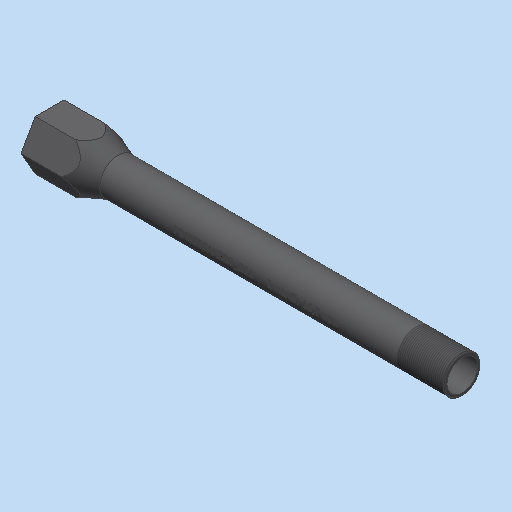
# Autodesk Inventor part: MN0555AN200_G11_100
Saved by Autodesk Inventor 2023.3 (Build 273359000, 359)
## iProperties
Created: 2012-10-29
Part Number: MN0555AN200_G11_100
Material: 1.2099 X5CrS12
Document SubType Name: Modeling
Designer: krt7an
Mass: 225.368 g
Surface Area: 273.759 cm^2
Volume: 28.7093 cm^3
Density: 7.85 g/cm^3
Description: =<RBPARTNOTITLE2>
Appearance: Stahl - rostfrei AnP
RBPARTNOTITLE1: manufactured part
RBPARTMADEOF: Ø31 x 220 (FM)
RBPARTNOTITLE2: Anfertigungsteil
RBPARTNO: SIEHE MNR
RBMATNO: =<Part Number>
RBMATERIAL: =<Material>
RBGBDIM_01: 0,000 mm
RBGBDIM_04: 0,000 mm
RBGBDIM_03: 0,000 mm
RBGBDIM_02: 0,000 mm
RBDRAWINGMISSINGSPEC: --
AnP_Kategorie: 1
RBGBREMARKSINDEX: E
RBSURFACE: --
AnP_Material: =<Material>
RBSURFACE2: --
MaxAbmaße: 26,847 x 31 x 220 (FM)
Author: krt7an
Keywords: =<RBPARTMADEOF>
Comments: =<RBSURFACE2>
Revision Number: 01
Autodesk Inventor part; units mm, degrees
ref_plane "YZ Plane" through (0, 0, 0) normal (1, 0, 0) x (0, 1, 0)
ref_plane "XY Plane" through (0, 0, 0) normal (0, 0, 1) x (1, 0, 0)
sketch "Skizze1" plane through (0, 0, 0) normal (0, 0, 1) x (1, 0, 0)
  line L0 (0, 0) -> (223, 0)
  line L1 (0, 0) -> (0, 10)
  line L2 (0, 10) -> (186, 10)
  line L3 (223, 0) -> (223, 15.5)
  line L4 (223, 15.5) -> (201.1111, 15.5)
  line L5 (201.1111, 15.5) -> (186, 10)
  dimension "d0" = 223
  dimension "d1" = 10
  dimension "d3" = 15.5
  dimension "d59" = 160
  dimension "d60" = 186
  constraints: 12 end point, 4 perpendicular, 1 horizontal
  measures "d0" distance of L0.start L0.end
  measures "d1" distance of L0.start L1.end
  measures "d3" distance of L0.end L3.end
  measures "d59" angle of L5 L2
  measures "d60" distance of L2.end L1.end
revolve "Umdrehung1" add sketch "Skizze1" angle 360 about axis through (0, 0, 0) along (1, 0, 0)
sketch "Skizze2" plane through (223, 0, 0) normal (1, 0, 0) x (0, 0, -1)
  circle A0 centre (0, 0) radius 15.5 projected
  line L0 (0, 15.5) -> (13.4234, 7.75)
  line L1 (13.4234, 7.75) -> (13.4234, -7.75)
  line L2 (13.4234, -7.75) -> (0, -15.5)
  line L3 (0, -15.5) -> (-13.4234, -7.75)
  line L4 (-13.4234, -7.75) -> (-13.4234, 7.75)
  line L5 (-13.4234, 7.75) -> (0, 15.5)
  line L6 (0, -21.7) -> (0, 21.7) projected
  constraints: 12 end point, 1 coincident, 1 point on line, 1 vertical alignment, 14 other
extrude "Extrusion1" cut sketch "Skizze2" against normal blind 30 contours A0 L1 | L0 A0 | A0 L2 | L5 A0 | A0 L3 | L4 A0
sketch "Skizze9" plane through (0, 0, 0) normal (-1, 0, 0) x (0, 0, 1)
  circle A0 centre (0, 0) radius 10 projected
  constraints: 1 coincident
hole "Bohrung1" at (0, 0, 0) direction (1, 0, 0) diameter 16.7 end through all
chamfer "Fase1" distance 0.5 angle 45 1 edges at (0, -10, 0)
sketch "Skizze11" plane through (223, -7.75, 13.4234) normal (1, 0, 0) x (0, 0, -1)
  circle A0 centre (13.4234, 7.75) radius 8.35 projected
  constraints: 1 coincident
hole "Bohrung2" at (223, 0, 0) direction (-1, 0, 0) diameter 19.177 depth 21 tip angle 118 thread size "7/8-9 UNC" class "2B" standard "ANSI Unified Screw Threads"
sketch "Skizze5" plane through (0, 0, 0) normal (0, 1, 0) x (-1, 0, 0)
  line L0 (40.4, 0) -> (-242.4, 0) projected
  line L1 (-202, 9.5885) -> (-202, -9.5885) projected
  line L2 (-201.2558, 8.35) -> (-201.2558, -8.35) projected
  line L3 (0, 8.35) -> (0, -8.35) projected
  line L4 (-202, 9.5885) -> (-188.4095, 1.4225)
  line L5 (-188.4095, 1.4225) -> (-188.4095, 0)
  line L6 (-202, 9.5885) -> (-202, 0)
  line L7 (-202, 0) -> (-188.4095, 0)
  point P0 (0, 0)
  dimension "d39" = 31
  dimension "d40" = 13.5905
  constraints: 8 end point, 1 collinear, 1 midpoint, 1 perpendicular, 1 point on line
  measures "d39" angle of L4 L0
  measures "d40" distance between parallel lines of L5 L1
revolve "Umdrehung2" cut sketch "Skizze5" angle 360 about axis through (-10, 0, 0) along (1, 0, 0)
thread "Gewinde4" size "M20x1" class "6g" standard "ISO Metric profile" length 25
sketch "Skizze7" plane through (223, -7.75, 13.4234) normal (1, 0, 0) x (0, 0, -1)
  circle A0 centre (13.4234, 7.75) radius 9.5885 projected
  circle A1 centre (13.4234, 7.75) radius 10
  dimension "d51" = 20
  constraints: 1 centre point, 1 coincident
  measures "d51" diameter of A1
extrude "Extrusion3" cut sketch "Skizze7" against normal blind 21
thread "Gewinde5" size "7/8-9 UNC" class "2B" standard "ANSI Unified Screw Threads" length 16
sketch "Skizze8" plane through (0, 0, 0) normal (-1, 0, 0) x (0, 0, 1)
  circle A0 centre (0, 0) radius 8.35 projected
  circle A1 centre (0, 0) radius 9.5 projected
  circle A2 centre (0, 0) radius 5.875
  dimension "d56" = 11.75
  constraints: 1 centre point, 1 coincident
  measures "d56" diameter of A2
extrude "Extrusion4" [suppressed]
ref_plane "Arbeitsebene3" through (93, 10, 0) normal (0, 1, 0) x (-1, 0, 0)
sketch "Skizze10" plane through (93, 10, 0) normal (0, 1, 0) x (-1, 0, 0)
  line L0 (-53, 2.25) -> (35.8221, 2.25) construction
  line L1 (35.8221, 2.25) -> (35.8221, -2.25) construction
  line L2 (35.8221, -2.25) -> (-53, -2.25) construction
  line L3 (-53, -2.25) -> (-53, 2.25) construction
  line L4 (-174.9, 0) -> (139.4, 0) projected
  line L5 (-93, 10) -> (-93, -10) projected
  line L6 (-49.6447, -1.4656) -> (-50.1098, -1.4656)
  line L7 (-50.1098, -1.4656) -> (-50.1098, 1.5494)
  line L8 (-50.1098, 1.5494) -> (-51.0231, -0.5012)
  line L9 (-51.0231, -0.5012) -> (-51.3067, -0.5012)
  line L10 (-51.3067, -0.5012) -> (-52.2115, 1.5494)
  line L11 (-52.2115, 1.5494) -> (-52.2115, -1.4656)
  line L12 (-52.2115, -1.4656) -> (-52.6455, -1.4656)
  line L13 (-52.6455, -1.4656) -> (-52.6455, 2.0344)
  line L14 (-52.6455, 2.0344) -> (-52.0101, 2.0344)
  line L15 (-52.0101, 2.0344) -> (-51.1365, 0.0859)
  line L16 (-51.1365, 0.0859) -> (-50.2913, 2.0344)
  line L17 (-50.2913, 2.0344) -> (-49.6447, 2.0344)
  line L18 (-49.6447, 2.0344) -> (-49.6447, -1.4656)
  line L19 (-45.9348, -1.4656) -> (-46.3999, -1.4656)
  line L20 (-46.3999, -1.4656) -> (-46.3999, 1.5494)
  line L21 (-46.3999, 1.5494) -> (-47.3132, -0.5012)
  line L22 (-47.3132, -0.5012) -> (-47.5968, -0.5012)
  line L23 (-47.5968, -0.5012) -> (-48.5016, 1.5494)
  line L24 (-48.5016, 1.5494) -> (-48.5016, -1.4656)
  line L25 (-48.5016, -1.4656) -> (-48.9356, -1.4656)
  line L26 (-48.9356, -1.4656) -> (-48.9356, 2.0344)
  line L27 (-48.9356, 2.0344) -> (-48.3002, 2.0344)
  line L28 (-48.3002, 2.0344) -> (-47.4267, 0.0859)
  line L29 (-47.4267, 0.0859) -> (-46.5814, 2.0344)
  line L30 (-46.5814, 2.0344) -> (-45.9348, 2.0344)
  line L31 (-45.9348, 2.0344) -> (-45.9348, -1.4656)
  spline S0 degree 2 poles (-43.1467, 0.2844) (-43.1467, -0.6572) (-43.6941, -1.5393) (-44.2642, -1.5393) knots 0 0 0 1 2 2 2
  spline S1 degree 2 poles (-44.2642, -1.5393) (-44.8428, -1.5393) (-45.3845, -0.6402) (-45.3845, 0.2816) knots 0 0 0 1 2 2 2
  spline S2 degree 2 poles (-45.3845, 0.2816) (-45.3845, 1.2289) (-44.8371, 2.1053) (-44.2642, 2.1053) knots 0 0 0 1 2 2 2
  spline S3 degree 2 poles (-44.2642, 2.1053) (-43.6884, 2.1053) (-43.1467, 1.1977) (-43.1467, 0.2844) knots 0 0 0 1 2 2 2
  spline S4 degree 2 poles (-43.748, -0.782) (-43.6799, -0.609) (-43.6232, -0.0758) (-43.6232, 0.2844) knots 0 0 0 1 2 2 2
  spline S5 degree 2 poles (-43.6232, 0.2844) (-43.6232, 0.6447) (-43.6799, 1.175) (-43.7508, 1.3537) knots 0 0 0 1 2 2 2
  spline S6 degree 2 poles (-43.7508, 1.3537) (-43.8217, 1.5324) (-44.0685, 1.7168) (-44.2642, 1.7168) knots 0 0 0 1 2 2 2
  spline S7 degree 2 poles (-44.2642, 1.7168) (-44.4599, 1.7168) (-44.7123, 1.5324) (-44.7861, 1.3481) knots 0 0 0 1 2 2 2
  spline S8 degree 2 poles (-44.7861, 1.3481) (-44.857, 1.1694) (-44.908, 0.6248) (-44.908, 0.2816) knots 0 0 0 1 2 2 2
  spline S9 degree 2 poles (-44.908, 0.2816) (-44.908, -0.0871) (-44.8626, -0.5806) (-44.7889, -0.7735) knots 0 0 0 1 2 2 2
  spline S10 degree 2 poles (-44.7889, -0.7735) (-44.7208, -0.955) (-44.4684, -1.1507) (-44.2642, -1.1507) knots 0 0 0 1 2 2 2
  spline S11 degree 2 poles (-44.2642, -1.1507) (-44.0713, -1.1507) (-43.8189, -0.9664) (-43.748, -0.782) knots 0 0 0 1 2 2 2
  spline S12 degree 2 poles (-40.577, -0.3537) (-40.577, -0.6062) (-40.7387, -1.0373) (-40.8861, -1.1961) knots 0 0 0 1 2 2 2
  spline S13 degree 2 poles (-40.8861, -1.1961) (-41.0336, -1.3549) (-41.4733, -1.5393) (-41.7455, -1.5393) knots 0 0 0 1 2 2 2
  spline S14 degree 2 poles (-41.7455, -1.5393) (-41.9951, -1.5393) (-42.483, -1.4287) (-42.6617, -1.3408) knots 0 0 0 1 2 2 2
  line L32 (-42.6617, -1.3408) -> (-42.6617, -0.8444)
  line L33 (-42.6617, -0.8444) -> (-42.6276, -0.8444)
  spline S15 degree 2 poles (-42.6276, -0.8444) (-42.5737, -0.8841) (-42.3724, -0.9862) (-42.2504, -1.0316) knots 0 0 0 1 2 2 2
  spline S16 degree 2 poles (-42.2504, -1.0316) (-42.1114, -1.0798) (-41.8817, -1.1337) (-41.737, -1.1337) knots 0 0 0 1 2 2 2
  spline S17 degree 2 poles (-41.737, -1.1337) (-41.5952, -1.1337) (-41.3286, -1.0316) (-41.2322, -0.921) knots 0 0 0 1 2 2 2
  spline S18 degree 2 poles (-41.2322, -0.921) (-41.1442, -0.816) (-41.0535, -0.5381) (-41.0535, -0.3509) knots 0 0 0 1 2 2 2
  spline S19 degree 2 poles (-41.0535, -0.3509) (-41.0535, -0.1637) (-41.1556, 0.0746) (-41.252, 0.154) knots 0 0 0 1 2 2 2
  spline S20 degree 2 poles (-41.252, 0.154) (-41.3513, 0.2419) (-41.6463, 0.3156) (-41.825, 0.3156) knots 0 0 0 1 2 2 2
  spline S21 degree 2 poles (-41.825, 0.3156) (-42.0178, 0.3156) (-42.4007, 0.2561) (-42.517, 0.2306) knots 0 0 0 1 2 2 2
  line L34 (-42.517, 0.2306) -> (-42.517, 2.0344)
  line L35 (-42.517, 2.0344) -> (-40.5968, 2.0344)
  line L36 (-40.5968, 2.0344) -> (-40.5968, 1.6232)
  line L37 (-40.5968, 1.6232) -> (-42.066, 1.6232)
  line L38 (-42.066, 1.6232) -> (-42.066, 0.69)
  spline S22 degree 2 poles (-42.066, 0.69) (-41.981, 0.7014) (-41.8165, 0.7099) (-41.7484, 0.7099) knots 0 0 0 1 2 2 2
  spline S23 degree 2 poles (-41.7484, 0.7099) (-41.4789, 0.7099) (-41.1074, 0.622) (-40.9372, 0.4915) knots 0 0 0 1 2 2 2
  spline S24 degree 2 poles (-40.9372, 0.4915) (-40.7642, 0.361) (-40.577, -0.0361) (-40.577, -0.3537) knots 0 0 0 1 2 2 2
  spline S25 degree 2 poles (-37.9506, -0.3537) (-37.9506, -0.6062) (-38.1122, -1.0373) (-38.2597, -1.1961) knots 0 0 0 1 2 2 2
  spline S26 degree 2 poles (-38.2597, -1.1961) (-38.4072, -1.3549) (-38.8468, -1.5393) (-39.1191, -1.5393) knots 0 0 0 1 2 2 2
  spline S27 degree 2 poles (-39.1191, -1.5393) (-39.3687, -1.5393) (-39.8566, -1.4287) (-40.0353, -1.3408) knots 0 0 0 1 2 2 2
  line L39 (-40.0353, -1.3408) -> (-40.0353, -0.8444)
  line L40 (-40.0353, -0.8444) -> (-40.0012, -0.8444)
  spline S28 degree 2 poles (-40.0012, -0.8444) (-39.9473, -0.8841) (-39.7459, -0.9862) (-39.624, -1.0316) knots 0 0 0 1 2 2 2
  spline S29 degree 2 poles (-39.624, -1.0316) (-39.485, -1.0798) (-39.2553, -1.1337) (-39.1106, -1.1337) knots 0 0 0 1 2 2 2
  spline S30 degree 2 poles (-39.1106, -1.1337) (-38.9688, -1.1337) (-38.7022, -1.0316) (-38.6058, -0.921) knots 0 0 0 1 2 2 2
  spline S31 degree 2 poles (-38.6058, -0.921) (-38.5178, -0.816) (-38.4271, -0.5381) (-38.4271, -0.3509) knots 0 0 0 1 2 2 2
  spline S32 degree 2 poles (-38.4271, -0.3509) (-38.4271, -0.1637) (-38.5292, 0.0746) (-38.6256, 0.154) knots 0 0 0 1 2 2 2
  spline S33 degree 2 poles (-38.6256, 0.154) (-38.7249, 0.2419) (-39.0199, 0.3156) (-39.1985, 0.3156) knots 0 0 0 1 2 2 2
  spline S34 degree 2 poles (-39.1985, 0.3156) (-39.3914, 0.3156) (-39.7743, 0.2561) (-39.8906, 0.2306) knots 0 0 0 1 2 2 2
  line L41 (-39.8906, 0.2306) -> (-39.8906, 2.0344)
  line L42 (-39.8906, 2.0344) -> (-37.9704, 2.0344)
  line L43 (-37.9704, 2.0344) -> (-37.9704, 1.6232)
  line L44 (-37.9704, 1.6232) -> (-39.4396, 1.6232)
  line L45 (-39.4396, 1.6232) -> (-39.4396, 0.69)
  spline S35 degree 2 poles (-39.4396, 0.69) (-39.3545, 0.7014) (-39.19, 0.7099) (-39.122, 0.7099) knots 0 0 0 1 2 2 2
  spline S36 degree 2 poles (-39.122, 0.7099) (-38.8525, 0.7099) (-38.481, 0.622) (-38.3108, 0.4915) knots 0 0 0 1 2 2 2
  spline S37 degree 2 poles (-38.3108, 0.4915) (-38.1378, 0.361) (-37.9506, -0.0361) (-37.9506, -0.3537) knots 0 0 0 1 2 2 2
  spline S38 degree 2 poles (-35.3241, -0.3537) (-35.3241, -0.6062) (-35.4858, -1.0373) (-35.6333, -1.1961) knots 0 0 0 1 2 2 2
  spline S39 degree 2 poles (-35.6333, -1.1961) (-35.7808, -1.3549) (-36.2204, -1.5393) (-36.4927, -1.5393) knots 0 0 0 1 2 2 2
  spline S40 degree 2 poles (-36.4927, -1.5393) (-36.7423, -1.5393) (-37.2301, -1.4287) (-37.4088, -1.3408) knots 0 0 0 1 2 2 2
  line L46 (-37.4088, -1.3408) -> (-37.4088, -0.8444)
  line L47 (-37.4088, -0.8444) -> (-37.3748, -0.8444)
  spline S41 degree 2 poles (-37.3748, -0.8444) (-37.3209, -0.8841) (-37.1195, -0.9862) (-36.9976, -1.0316) knots 0 0 0 1 2 2 2
  spline S42 degree 2 poles (-36.9976, -1.0316) (-36.8586, -1.0798) (-36.6288, -1.1337) (-36.4842, -1.1337) knots 0 0 0 1 2 2 2
  spline S43 degree 2 poles (-36.4842, -1.1337) (-36.3424, -1.1337) (-36.0758, -1.0316) (-35.9793, -0.921) knots 0 0 0 1 2 2 2
  spline S44 degree 2 poles (-35.9793, -0.921) (-35.8914, -0.816) (-35.8006, -0.5381) (-35.8006, -0.3509) knots 0 0 0 1 2 2 2
  spline S45 degree 2 poles (-35.8006, -0.3509) (-35.8006, -0.1637) (-35.9028, 0.0746) (-35.9992, 0.154) knots 0 0 0 1 2 2 2
  spline S46 degree 2 poles (-35.9992, 0.154) (-36.0985, 0.2419) (-36.3934, 0.3156) (-36.5721, 0.3156) knots 0 0 0 1 2 2 2
  spline S47 degree 2 poles (-36.5721, 0.3156) (-36.765, 0.3156) (-37.1479, 0.2561) (-37.2642, 0.2306) knots 0 0 0 1 2 2 2
  line L48 (-37.2642, 0.2306) -> (-37.2642, 2.0344)
  line L49 (-37.2642, 2.0344) -> (-35.344, 2.0344)
  line L50 (-35.344, 2.0344) -> (-35.344, 1.6232)
  line L51 (-35.344, 1.6232) -> (-36.8132, 1.6232)
  line L52 (-36.8132, 1.6232) -> (-36.8132, 0.69)
  spline S48 degree 2 poles (-36.8132, 0.69) (-36.7281, 0.7014) (-36.5636, 0.7099) (-36.4955, 0.7099) knots 0 0 0 1 2 2 2
  spline S49 degree 2 poles (-36.4955, 0.7099) (-36.2261, 0.7099) (-35.8545, 0.622) (-35.6844, 0.4915) knots 0 0 0 1 2 2 2
  spline S50 degree 2 poles (-35.6844, 0.4915) (-35.5113, 0.361) (-35.3241, -0.0361) (-35.3241, -0.3537) knots 0 0 0 1 2 2 2
  line L53 (-35.0972, -1.4656) -> (-33.9173, 2.0344)
  line L54 (-33.9173, 2.0344) -> (-33.3444, 2.0344)
  line L55 (-33.3444, 2.0344) -> (-32.1645, -1.4656)
  line L56 (-32.1645, -1.4656) -> (-32.6552, -1.4656)
  line L57 (-32.6552, -1.4656) -> (-32.9729, -0.487)
  line L58 (-32.9729, -0.487) -> (-34.3088, -0.487)
  line L59 (-34.3088, -0.487) -> (-34.6264, -1.4656)
  line L60 (-34.6264, -1.4656) -> (-35.0972, -1.4656)
  line L61 (-33.1005, -0.09) -> (-33.6422, 1.5579)
  line L62 (-33.6422, 1.5579) -> (-34.1811, -0.09)
  line L63 (-34.1811, -0.09) -> (-33.1005, -0.09)
  line L64 (-29.3282, -1.4656) -> (-29.8501, -1.4656)
  line L65 (-29.8501, -1.4656) -> (-31.3987, 1.5523)
  line L66 (-31.3987, 1.5523) -> (-31.3987, -1.4656)
  line L67 (-31.3987, -1.4656) -> (-31.8327, -1.4656)
  line L68 (-31.8327, -1.4656) -> (-31.8327, 2.0344)
  line L69 (-31.8327, 2.0344) -> (-31.1718, 2.0344)
  line L70 (-31.1718, 2.0344) -> (-29.7622, -0.7366)
  line L71 (-29.7622, -0.7366) -> (-29.7622, 2.0344)
  line L72 (-29.7622, 2.0344) -> (-29.3282, 2.0344)
  line L73 (-29.3282, 2.0344) -> (-29.3282, -1.4656)
  line L74 (-26.56, -1.4656) -> (-28.7184, -1.4656)
  line L75 (-28.7184, -1.4656) -> (-28.7184, -0.9692)
  spline S51 degree 2 poles (-28.7184, -0.9692) (-28.4858, -0.7508) (-28.0717, -0.3452) (-27.8732, -0.1268) knots 0 0 0 1 2 2 2
  spline S52 degree 2 poles (-27.8732, -0.1268) (-27.4733, 0.3128) (-27.1811, 0.8404) (-27.1811, 1.1212) knots 0 0 0 1 2 2 2
  spline S53 degree 2 poles (-27.1811, 1.1212) (-27.1811, 1.2686) (-27.2719, 1.4899) (-27.3541, 1.5608) knots 0 0 0 1 2 2 2
  spline S54 degree 2 poles (-27.3541, 1.5608) (-27.4364, 1.6317) (-27.6519, 1.7026) (-27.7824, 1.7026) knots 0 0 0 1 2 2 2
  spline S55 degree 2 poles (-27.7824, 1.7026) (-27.9072, 1.7026) (-28.1625, 1.6402) (-28.2788, 1.592) knots 0 0 0 1 2 2 2
  spline S56 degree 2 poles (-28.2788, 1.592) (-28.378, 1.5523) (-28.5624, 1.4388) (-28.6191, 1.3991) knots 0 0 0 1 2 2 2
  line L76 (-28.6191, 1.3991) -> (-28.6447, 1.3991)
  line L77 (-28.6447, 1.3991) -> (-28.6447, 1.8983)
  spline S57 degree 2 poles (-28.6447, 1.8983) (-28.5, 1.9692) (-27.981, 2.1082) (-27.7484, 2.1082) knots 0 0 0 1 2 2 2
  spline S58 degree 2 poles (-27.7484, 2.1082) (-27.2577, 2.1082) (-26.7046, 1.5891) (-26.7046, 1.1467) knots 0 0 0 1 2 2 2
  spline S59 degree 2 poles (-26.7046, 1.1467) (-26.7046, 0.9396) (-26.8011, 0.5936) (-26.8861, 0.4461) knots 0 0 0 1 2 2 2
  spline S60 degree 2 poles (-26.8861, 0.4461) (-26.9712, 0.2929) (-27.218, -0.0077) (-27.3541, -0.1524) knots 0 0 0 1 2 2 2
  spline S61 degree 2 poles (-27.3541, -0.1524) (-27.5754, -0.3934) (-28.1171, -0.9096) (-28.2788, -1.06) knots 0 0 0 1 2 2 2
  line L78 (-28.2788, -1.06) -> (-26.56, -1.06)
  line L79 (-26.56, -1.06) -> (-26.56, -1.4656)
  spline S62 degree 2 poles (-23.9137, 0.2844) (-23.9137, -0.6572) (-24.4611, -1.5393) (-25.0312, -1.5393) knots 0 0 0 1 2 2 2
  spline S63 degree 2 poles (-25.0312, -1.5393) (-25.6098, -1.5393) (-26.1515, -0.6402) (-26.1515, 0.2816) knots 0 0 0 1 2 2 2
  spline S64 degree 2 poles (-26.1515, 0.2816) (-26.1515, 1.2289) (-25.6041, 2.1053) (-25.0312, 2.1053) knots 0 0 0 1 2 2 2
  spline S65 degree 2 poles (-25.0312, 2.1053) (-24.4554, 2.1053) (-23.9137, 1.1977) (-23.9137, 0.2844) knots 0 0 0 1 2 2 2
  spline S66 degree 2 poles (-24.515, -0.782) (-24.4469, -0.609) (-24.3902, -0.0758) (-24.3902, 0.2844) knots 0 0 0 1 2 2 2
  spline S67 degree 2 poles (-24.3902, 0.2844) (-24.3902, 0.6447) (-24.4469, 1.175) (-24.5178, 1.3537) knots 0 0 0 1 2 2 2
  spline S68 degree 2 poles (-24.5178, 1.3537) (-24.5887, 1.5324) (-24.8355, 1.7168) (-25.0312, 1.7168) knots 0 0 0 1 2 2 2
  spline S69 degree 2 poles (-25.0312, 1.7168) (-25.2269, 1.7168) (-25.4793, 1.5324) (-25.5531, 1.3481) knots 0 0 0 1 2 2 2
  spline S70 degree 2 poles (-25.5531, 1.3481) (-25.624, 1.1694) (-25.675, 0.6248) (-25.675, 0.2816) knots 0 0 0 1 2 2 2
  spline S71 degree 2 poles (-25.675, 0.2816) (-25.675, -0.0871) (-25.6297, -0.5806) (-25.5559, -0.7735) knots 0 0 0 1 2 2 2
  spline S72 degree 2 poles (-25.5559, -0.7735) (-25.4878, -0.955) (-25.2354, -1.1507) (-25.0312, -1.1507) knots 0 0 0 1 2 2 2
  spline S73 degree 2 poles (-25.0312, -1.1507) (-24.8383, -1.1507) (-24.5859, -0.9664) (-24.515, -0.782) knots 0 0 0 1 2 2 2
  spline S74 degree 2 poles (-21.2873, 0.2844) (-21.2873, -0.6572) (-21.8347, -1.5393) (-22.4048, -1.5393) knots 0 0 0 1 2 2 2
  spline S75 degree 2 poles (-22.4048, -1.5393) (-22.9834, -1.5393) (-23.5251, -0.6402) (-23.5251, 0.2816) knots 0 0 0 1 2 2 2
  spline S76 degree 2 poles (-23.5251, 0.2816) (-23.5251, 1.2289) (-22.9777, 2.1053) (-22.4048, 2.1053) knots 0 0 0 1 2 2 2
  spline S77 degree 2 poles (-22.4048, 2.1053) (-21.829, 2.1053) (-21.2873, 1.1977) (-21.2873, 0.2844) knots 0 0 0 1 2 2 2
  spline S78 degree 2 poles (-21.8886, -0.782) (-21.8205, -0.609) (-21.7638, -0.0758) (-21.7638, 0.2844) knots 0 0 0 1 2 2 2
  spline S79 degree 2 poles (-21.7638, 0.2844) (-21.7638, 0.6447) (-21.8205, 1.175) (-21.8914, 1.3537) knots 0 0 0 1 2 2 2
  spline S80 degree 2 poles (-21.8914, 1.3537) (-21.9623, 1.5324) (-22.2091, 1.7168) (-22.4048, 1.7168) knots 0 0 0 1 2 2 2
  spline S81 degree 2 poles (-22.4048, 1.7168) (-22.6005, 1.7168) (-22.8529, 1.5324) (-22.9267, 1.3481) knots 0 0 0 1 2 2 2
  spline S82 degree 2 poles (-22.9267, 1.3481) (-22.9976, 1.1694) (-23.0486, 0.6248) (-23.0486, 0.2816) knots 0 0 0 1 2 2 2
  spline S83 degree 2 poles (-23.0486, 0.2816) (-23.0486, -0.0871) (-23.0032, -0.5806) (-22.9295, -0.7735) knots 0 0 0 1 2 2 2
  spline S84 degree 2 poles (-22.9295, -0.7735) (-22.8614, -0.955) (-22.609, -1.1507) (-22.4048, -1.1507) knots 0 0 0 1 2 2 2
  spline S85 degree 2 poles (-22.4048, -1.1507) (-22.2119, -1.1507) (-21.9595, -0.9664) (-21.8886, -0.782) knots 0 0 0 1 2 2 2
  line L80 (-18.4311, -2.169) -> (-21.1313, -2.169)
  line L81 (-21.1313, -2.169) -> (-21.1313, -1.8655)
  line L82 (-21.1313, -1.8655) -> (-18.4311, -1.8655)
  line L83 (-18.4311, -1.8655) -> (-18.4311, -2.169)
  spline S86 degree 2 poles (-16.6471, -1.5336) (-17.0186, -1.5336) (-17.6341, -1.3067) (-17.8553, -1.077) knots 0 0 0 1 2 2 2
  spline S87 degree 2 poles (-17.8553, -1.077) (-18.0766, -0.8444) (-18.312, -0.158) (-18.312, 0.2873) knots 0 0 0 1 2 2 2
  spline S88 degree 2 poles (-18.312, 0.2873) (-18.312, 0.7099) (-18.0737, 1.3793) (-17.8525, 1.6175) knots 0 0 0 1 2 2 2
  spline S89 degree 2 poles (-17.8525, 1.6175) (-17.6398, 1.8472) (-17.0158, 2.0968) (-16.6442, 2.0968) knots 0 0 0 1 2 2 2
  spline S90 degree 2 poles (-16.6442, 2.0968) (-16.4656, 2.0968) (-16.1422, 2.0458) (-15.9947, 2.0004) knots 0 0 0 1 2 2 2
  spline S91 degree 2 poles (-15.9947, 2.0004) (-15.8756, 1.9664) (-15.5863, 1.8416) (-15.4984, 1.7962) knots 0 0 0 1 2 2 2
  line L84 (-15.4984, 1.7962) -> (-15.4984, 1.2346)
  line L85 (-15.4984, 1.2346) -> (-15.5381, 1.2346)
  spline S92 degree 2 poles (-15.5381, 1.2346) (-15.626, 1.3112) (-15.8104, 1.4502) (-15.9806, 1.5296) knots 0 0 0 1 2 2 2
  spline S93 degree 2 poles (-15.9806, 1.5296) (-16.1224, 1.6005) (-16.4883, 1.6941) (-16.6981, 1.6941) knots 0 0 0 1 2 2 2
  spline S94 degree 2 poles (-16.6981, 1.6941) (-17.203, 1.6941) (-17.827, 0.934) (-17.827, 0.3015) knots 0 0 0 1 2 2 2
  spline S95 degree 2 poles (-17.827, 0.3015) (-17.827, -0.0502) (-17.6625, -0.5778) (-17.5065, -0.7593) knots 0 0 0 1 2 2 2
  spline S96 degree 2 poles (-17.5065, -0.7593) (-17.3562, -0.9408) (-16.9307, -1.1309) (-16.6641, -1.1309) knots 0 0 0 1 2 2 2
  spline S97 degree 2 poles (-16.6641, -1.1309) (-16.4684, -1.1309) (-16.077, -1.0741) (-15.9437, -1.0174) knots 0 0 0 1 2 2 2
  line L86 (-15.9437, -1.0174) -> (-15.9437, -0.1126)
  line L87 (-15.9437, -0.1126) -> (-16.7549, -0.1126)
  line L88 (-16.7549, -0.1126) -> (-16.7549, 0.2958)
  line L89 (-16.7549, 0.2958) -> (-15.4842, 0.2958)
  line L90 (-15.4842, 0.2958) -> (-15.4842, -1.233)
  spline S98 degree 2 poles (-15.4842, -1.233) (-15.5721, -1.2727) (-15.8728, -1.3947) (-16.0004, -1.4315) knots 0 0 0 1 2 2 2
  spline S99 degree 2 poles (-16.0004, -1.4315) (-16.1734, -1.4826) (-16.4514, -1.5336) (-16.6471, -1.5336) knots 0 0 0 1 2 2 2
  line L91 (-13.0166, -1.4656) -> (-14.7241, -1.4656)
  line L92 (-14.7241, -1.4656) -> (-14.7241, -1.1082)
  line L93 (-14.7241, -1.1082) -> (-14.0887, -1.1082)
  line L94 (-14.0887, -1.1082) -> (-14.0887, 1.2374)
  line L95 (-14.0887, 1.2374) -> (-14.7241, 1.2374)
  line L96 (-14.7241, 1.2374) -> (-14.7241, 1.5579)
  spline S100 degree 2 poles (-14.7241, 1.5579) (-14.3639, 1.5579) (-14.0235, 1.7622) (-14.0008, 2.0458) knots 0 0 0 1 2 2 2
  line L97 (-14.0008, 2.0458) -> (-13.6378, 2.0458)
  line L98 (-13.6378, 2.0458) -> (-13.6378, -1.1082)
  line L99 (-13.6378, -1.1082) -> (-13.0166, -1.1082)
  line L100 (-13.0166, -1.1082) -> (-13.0166, -1.4656)
  line L101 (-10.3902, -1.4656) -> (-12.0977, -1.4656)
  line L102 (-12.0977, -1.4656) -> (-12.0977, -1.1082)
  line L103 (-12.0977, -1.1082) -> (-11.4623, -1.1082)
  line L104 (-11.4623, -1.1082) -> (-11.4623, 1.2374)
  line L105 (-11.4623, 1.2374) -> (-12.0977, 1.2374)
  line L106 (-12.0977, 1.2374) -> (-12.0977, 1.5579)
  spline S101 degree 2 poles (-12.0977, 1.5579) (-11.7374, 1.5579) (-11.3971, 1.7622) (-11.3744, 2.0458) knots 0 0 0 1 2 2 2
  line L107 (-11.3744, 2.0458) -> (-11.0113, 2.0458)
  line L108 (-11.0113, 2.0458) -> (-11.0113, -1.1082)
  line L109 (-11.0113, -1.1082) -> (-10.3902, -1.1082)
  line L110 (-10.3902, -1.1082) -> (-10.3902, -1.4656)
  line L111 (-0.9113, -1.4656) -> (-2.267, -1.4656)
  line L112 (-2.267, -1.4656) -> (-2.267, -1.1082)
  line L113 (-2.267, -1.1082) -> (-1.8217, -1.1082)
  line L114 (-1.8217, -1.1082) -> (-1.8217, 1.6771)
  line L115 (-1.8217, 1.6771) -> (-2.267, 1.6771)
  line L116 (-2.267, 1.6771) -> (-2.267, 2.0344)
  line L117 (-2.267, 2.0344) -> (-0.9113, 2.0344)
  line L118 (-0.9113, 2.0344) -> (-0.9113, 1.6771)
  line L119 (-0.9113, 1.6771) -> (-1.3566, 1.6771)
  line L120 (-1.3566, 1.6771) -> (-1.3566, -1.1082)
  line L121 (-1.3566, -1.1082) -> (-0.9113, -1.1082)
  line L122 (-0.9113, -1.1082) -> (-0.9113, -1.4656)
  line L123 (1.6925, -1.4656) -> (1.25, -1.4656)
  line L124 (1.25, -1.4656) -> (1.25, 0.032)
  spline S102 degree 2 poles (1.25, 0.032) (1.25, 0.2135) (1.216, 0.5255) (1.1649, 0.6191) knots 0 0 0 1 2 2 2
  spline S103 degree 2 poles (1.1649, 0.6191) (1.111, 0.7184) (0.9182, 0.8148) (0.7536, 0.8148) knots 0 0 0 1 2 2 2
  spline S104 degree 2 poles (0.7536, 0.8148) (0.5891, 0.8148) (0.2403, 0.639) (0.0729, 0.4972) knots 0 0 0 1 2 2 2
  line L125 (0.0729, 0.4972) -> (0.0729, -1.4656)
  line L126 (0.0729, -1.4656) -> (-0.3695, -1.4656)
  line L127 (-0.3695, -1.4656) -> (-0.3695, 1.1609)
  line L128 (-0.3695, 1.1609) -> (0.0729, 1.1609)
  line L129 (0.0729, 1.1609) -> (0.0729, 0.8687)
  spline S105 degree 2 poles (0.0729, 0.8687) (0.2715, 1.0474) (0.6544, 1.2346) (0.8699, 1.2346) knots 0 0 0 1 2 2 2
  spline S106 degree 2 poles (0.8699, 1.2346) (1.2557, 1.2346) (1.6925, 0.7241) (1.6925, 0.2391) knots 0 0 0 1 2 2 2
  line L130 (1.6925, 0.2391) -> (1.6925, -1.4656)
  line L131 (4.3756, -1.4656) -> (3.9331, -1.4656)
  line L132 (3.9331, -1.4656) -> (3.9331, 0.032)
  spline S107 degree 2 poles (3.9331, 0.032) (3.9331, 0.2135) (3.8991, 0.5255) (3.8481, 0.6191) knots 0 0 0 1 2 2 2
  spline S108 degree 2 poles (3.8481, 0.6191) (3.7942, 0.7184) (3.6013, 0.8148) (3.4368, 0.8148) knots 0 0 0 1 2 2 2
  spline S109 degree 2 poles (3.4368, 0.8148) (3.2723, 0.8148) (2.9234, 0.639) (2.7561, 0.4972) knots 0 0 0 1 2 2 2
  line L133 (2.7561, 0.4972) -> (2.7561, -1.4656)
  line L134 (2.7561, -1.4656) -> (2.3136, -1.4656)
  line L135 (2.3136, -1.4656) -> (2.3136, 1.1609)
  line L136 (2.3136, 1.1609) -> (2.7561, 1.1609)
  line L137 (2.7561, 1.1609) -> (2.7561, 0.8687)
  spline S110 degree 2 poles (2.7561, 0.8687) (2.9546, 1.0474) (3.3375, 1.2346) (3.5531, 1.2346) knots 0 0 0 1 2 2 2
  spline S111 degree 2 poles (3.5531, 1.2346) (3.9388, 1.2346) (4.3756, 0.7241) (4.3756, 0.2391) knots 0 0 0 1 2 2 2
  line L138 (4.3756, 0.2391) -> (4.3756, -1.4656)
  spline S112 degree 2 poles (6.137, -1.5251) (5.5073, -1.5251) (4.8152, -0.8189) (4.8152, -0.1665) knots 0 0 0 1 2 2 2
  spline S113 degree 2 poles (4.8152, -0.1665) (4.8152, 0.4745) (5.4874, 1.2346) (6.0292, 1.2346) knots 0 0 0 1 2 2 2
  spline S114 degree 2 poles (6.0292, 1.2346) (6.2731, 1.2346) (6.6503, 1.0928) (6.7893, 0.9425) knots 0 0 0 1 2 2 2
  spline S115 degree 2 poles (6.7893, 0.9425) (6.9311, 0.7921) (7.0814, 0.3582) (7.0814, 0.0434) knots 0 0 0 1 2 2 2
  line L139 (7.0814, 0.0434) -> (7.0814, -0.1977)
  line L140 (7.0814, -0.1977) -> (5.2634, -0.1977)
  spline S116 degree 2 poles (5.2634, -0.1977) (5.2634, -0.6544) (5.7229, -1.1394) (6.1313, -1.1394) knots 0 0 0 1 2 2 2
  spline S117 degree 2 poles (6.1313, -1.1394) (6.2759, -1.1394) (6.5567, -1.0741) (6.6702, -1.0231) knots 0 0 0 1 2 2 2
  spline S118 degree 2 poles (6.6702, -1.0231) (6.7893, -0.9664) (6.9538, -0.8671) (7.0077, -0.8217) knots 0 0 0 1 2 2 2
  line L141 (7.0077, -0.8217) -> (7.0332, -0.8217)
  line L142 (7.0332, -0.8217) -> (7.0332, -1.3039)
  spline S119 degree 2 poles (7.0332, -1.3039) (6.9566, -1.3351) (6.7241, -1.4259) (6.6333, -1.4514) knots 0 0 0 1 2 2 2
  spline S120 degree 2 poles (6.6333, -1.4514) (6.5057, -1.4882) (6.2958, -1.5251) (6.137, -1.5251) knots 0 0 0 1 2 2 2
  spline S121 degree 2 poles (6.6503, 0.1398) (6.6447, 0.3185) (6.5709, 0.5794) (6.5, 0.6673) knots 0 0 0 1 2 2 2
  spline S122 degree 2 poles (6.5, 0.6673) (6.4234, 0.7666) (6.1823, 0.8716) (6.0036, 0.8716) knots 0 0 0 1 2 2 2
  spline S123 degree 2 poles (6.0036, 0.8716) (5.8278, 0.8716) (5.581, 0.7666) (5.4789, 0.6645) knots 0 0 0 1 2 2 2
  spline S124 degree 2 poles (5.4789, 0.6645) (5.3797, 0.5596) (5.2776, 0.3071) (5.2634, 0.1398) knots 0 0 0 1 2 2 2
  line L143 (5.2634, 0.1398) -> (6.6503, 0.1398)
  line L144 (9.5916, -1.4656) -> (9.1491, -1.4656)
  line L145 (9.1491, -1.4656) -> (9.1491, 0.032)
  spline S125 degree 2 poles (9.1491, 0.032) (9.1491, 0.2135) (9.1151, 0.5255) (9.064, 0.6191) knots 0 0 0 1 2 2 2
  spline S126 degree 2 poles (9.064, 0.6191) (9.0101, 0.7184) (8.8173, 0.8148) (8.6528, 0.8148) knots 0 0 0 1 2 2 2
  spline S127 degree 2 poles (8.6528, 0.8148) (8.4882, 0.8148) (8.1394, 0.639) (7.972, 0.4972) knots 0 0 0 1 2 2 2
  line L146 (7.972, 0.4972) -> (7.972, -1.4656)
  line L147 (7.972, -1.4656) -> (7.5296, -1.4656)
  line L148 (7.5296, -1.4656) -> (7.5296, 1.1609)
  line L149 (7.5296, 1.1609) -> (7.972, 1.1609)
  line L150 (7.972, 1.1609) -> (7.972, 0.8687)
  spline S128 degree 2 poles (7.972, 0.8687) (8.1706, 1.0474) (8.5535, 1.2346) (8.769, 1.2346) knots 0 0 0 1 2 2 2
  spline S129 degree 2 poles (8.769, 1.2346) (9.1548, 1.2346) (9.5916, 0.7241) (9.5916, 0.2391) knots 0 0 0 1 2 2 2
  line L151 (9.5916, 0.2391) -> (9.5916, -1.4656)
  spline S130 degree 2 poles (13.1426, 0.2844) (13.1426, -0.5835) (12.2974, -1.5393) (11.594, -1.5393) knots 0 0 0 1 2 2 2
  spline S131 degree 2 poles (11.594, -1.5393) (11.3359, -1.5393) (10.8906, -1.4032) (10.7119, -1.2784) knots 0 0 0 1 2 2 2
  line L152 (10.7119, -1.2784) -> (10.3999, -1.7378)
  line L153 (10.3999, -1.7378) -> (10.0539, -1.7378)
  line L154 (10.0539, -1.7378) -> (10.4964, -1.0855)
  spline S132 degree 2 poles (10.4964, -1.0855) (10.2865, -0.8529) (10.0482, -0.1665) (10.0482, 0.2844) knots 0 0 0 1 2 2 2
  spline S133 degree 2 poles (10.0482, 0.2844) (10.0482, 1.1495) (10.8963, 2.1082) (11.594, 2.1082) knots 0 0 0 1 2 2 2
  spline S134 degree 2 poles (11.594, 2.1082) (11.8635, 2.1082) (12.2832, 1.9777) (12.4704, 1.8501) knots 0 0 0 1 2 2 2
  line L155 (12.4704, 1.8501) -> (12.7399, 2.25)
  line L156 (12.7399, 2.25) -> (13.0887, 2.25)
  line L157 (13.0887, 2.25) -> (12.686, 1.66)
  spline S135 degree 2 poles (12.686, 1.66) (12.9015, 1.4275) (13.1426, 0.7524) (13.1426, 0.2844) knots 0 0 0 1 2 2 2
  spline S136 degree 2 poles (12.6633, 0.2844) (12.6633, 0.6078) (12.5328, 1.1155) (12.425, 1.2828) knots 0 0 0 1 2 2 2
  line L158 (12.425, 1.2828) -> (10.9502, -0.921)
  spline S137 degree 2 poles (10.9502, -0.921) (11.0835, -1.0288) (11.3841, -1.1365) (11.5968, -1.1365) knots 0 0 0 1 2 2 2
  spline S138 degree 2 poles (11.5968, -1.1365) (12.0818, -1.1365) (12.6633, -0.4048) (12.6633, 0.2844) knots 0 0 0 1 2 2 2
  spline S139 degree 2 poles (12.2322, 1.4955) (12.1102, 1.6005) (11.7897, 1.7054) (11.5968, 1.7054) knots 0 0 0 1 2 2 2
  spline S140 degree 2 poles (11.5968, 1.7054) (11.109, 1.7054) (10.5276, 0.9822) (10.5276, 0.2844) knots 0 0 0 1 2 2 2
  spline S141 degree 2 poles (10.5276, 0.2844) (10.5276, -0.0332) (10.6495, -0.5267) (10.7601, -0.7026) knots 0 0 0 1 2 2 2
  line L159 (10.7601, -0.7026) -> (12.2322, 1.4955)
  line L160 (14.4303, -1.4656) -> (13.8687, -1.4656)
  line L161 (13.8687, -1.4656) -> (13.8687, -0.7962)
  line L162 (13.8687, -0.7962) -> (14.4303, -0.7962)
  line L163 (14.4303, -0.7962) -> (14.4303, -1.4656)
  line L164 (14.4303, 0.4915) -> (13.8687, 0.4915)
  line L165 (13.8687, 0.4915) -> (13.8687, 1.1609)
  line L166 (13.8687, 1.1609) -> (14.4303, 1.1609)
  line L167 (14.4303, 1.1609) -> (14.4303, 0.4915)
  line L168 (18.7415, -1.4656) -> (17.034, -1.4656)
  line L169 (17.034, -1.4656) -> (17.034, -1.1082)
  line L170 (17.034, -1.1082) -> (17.6694, -1.1082)
  line L171 (17.6694, -1.1082) -> (17.6694, 1.2374)
  line L172 (17.6694, 1.2374) -> (17.034, 1.2374)
  line L173 (17.034, 1.2374) -> (17.034, 1.5579)
  spline S142 degree 2 poles (17.034, 1.5579) (17.3942, 1.5579) (17.7346, 1.7622) (17.7573, 2.0458) knots 0 0 0 1 2 2 2
  line L174 (17.7573, 2.0458) -> (18.1203, 2.0458)
  line L175 (18.1203, 2.0458) -> (18.1203, -1.1082)
  line L176 (18.1203, -1.1082) -> (18.7415, -1.1082)
  line L177 (18.7415, -1.1082) -> (18.7415, -1.4656)
  spline S143 degree 2 poles (21.5976, -0.331) (21.5976, -0.6005) (21.419, -1.0571) (21.2686, -1.2103) knots 0 0 0 1 2 2 2
  spline S144 degree 2 poles (21.2686, -1.2103) (21.1126, -1.372) (20.7212, -1.5393) (20.4858, -1.5393) knots 0 0 0 1 2 2 2
  spline S145 degree 2 poles (20.4858, -1.5393) (20.2504, -1.5393) (19.8618, -1.3805) (19.7143, -1.2216) knots 0 0 0 1 2 2 2
  spline S146 degree 2 poles (19.7143, -1.2216) (19.5328, -1.0316) (19.3286, -0.3934) (19.3286, 0.0717) knots 0 0 0 1 2 2 2
  spline S147 degree 2 poles (19.3286, 0.0717) (19.3286, 0.5284) (19.5158, 1.263) (19.7115, 1.5353) knots 0 0 0 1 2 2 2
  spline S148 degree 2 poles (19.7115, 1.5353) (19.9015, 1.8019) (20.5028, 2.0997) (20.8971, 2.0997) knots 0 0 0 1 2 2 2
  spline S149 degree 2 poles (20.8971, 2.0997) (21.0134, 2.0997) (21.2176, 2.077) (21.2942, 2.0515) knots 0 0 0 1 2 2 2
  line L178 (21.2942, 2.0515) -> (21.2942, 1.6005)
  line L179 (21.2942, 1.6005) -> (21.2743, 1.6005)
  spline S150 degree 2 poles (21.2743, 1.6005) (21.2091, 1.6345) (20.9708, 1.6941) (20.8347, 1.6941) knots 0 0 0 1 2 2 2
  spline S151 degree 2 poles (20.8347, 1.6941) (20.3979, 1.6941) (19.8618, 1.1041) (19.8108, 0.5255) knots 0 0 0 1 2 2 2
  spline S152 degree 2 poles (19.8108, 0.5255) (19.9781, 0.6418) (20.3298, 0.7694) (20.5397, 0.7694) knots 0 0 0 1 2 2 2
  spline S153 degree 2 poles (20.5397, 0.7694) (20.7439, 0.7694) (21.0502, 0.6872) (21.2176, 0.5624) knots 0 0 0 1 2 2 2
  spline S154 degree 2 poles (21.2176, 0.5624) (21.4105, 0.4177) (21.5976, -0.0304) (21.5976, -0.331) knots 0 0 0 1 2 2 2
  spline S155 degree 2 poles (21.1211, -0.3509) (21.1211, -0.1353) (21.0077, 0.1568) (20.8829, 0.2589) knots 0 0 0 1 2 2 2
  spline S156 degree 2 poles (20.8829, 0.2589) (20.7893, 0.3327) (20.5567, 0.3809) (20.4348, 0.3809) knots 0 0 0 1 2 2 2
  spline S157 degree 2 poles (20.4348, 0.3809) (20.2703, 0.3809) (19.9611, 0.2816) (19.8108, 0.188) knots 0 0 0 1 2 2 2
  spline S158 degree 2 poles (19.8108, 0.188) (19.8079, 0.137) (19.8023, 0.0405) (19.8023, -0.0332) knots 0 0 0 1 2 2 2
  spline S159 degree 2 poles (19.8023, -0.0332) (19.8023, -0.3963) (19.9441, -0.8416) (20.0519, -0.9579) knots 0 0 0 1 2 2 2
  spline S160 degree 2 poles (20.0519, -0.9579) (20.1511, -1.0685) (20.3667, -1.1564) (20.4887, -1.1564) knots 0 0 0 1 2 2 2
  spline S161 degree 2 poles (20.4887, -1.1564) (20.7723, -1.1564) (21.1211, -0.7536) (21.1211, -0.3509) knots 0 0 0 1 2 2 2
  line L180 (22.9307, -0.7962) -> (22.2727, -2.3363)
  line L181 (22.2727, -2.3363) -> (21.9295, -2.3363)
  line L182 (21.9295, -2.3363) -> (22.3436, -0.7962)
  line L183 (22.3436, -0.7962) -> (22.9307, -0.7962)
  line L184 (25.6677, 1.5097) -> (24.1532, -1.4656)
  line L185 (24.1532, -1.4656) -> (23.654, -1.4656)
  line L186 (23.654, -1.4656) -> (25.2536, 1.6232)
  line L187 (25.2536, 1.6232) -> (23.4469, 1.6232)
  line L188 (23.4469, 1.6232) -> (23.4469, 2.0344)
  line L189 (23.4469, 2.0344) -> (25.6677, 2.0344)
  line L190 (25.6677, 2.0344) -> (25.6677, 1.5097)
  line L191 (30.6426, -1.4656) -> (30.6426, 0.0547)
  spline S162 degree 2 poles (30.6426, 0.0547) (30.6426, 0.2362) (30.6143, 0.5454) (30.5689, 0.6305) knots 0 0 0 1 2 2 2
  spline S163 degree 2 poles (30.5689, 0.6305) (30.5235, 0.7241) (30.3505, 0.8148) (30.2002, 0.8148) knots 0 0 0 1 2 2 2
  spline S164 degree 2 poles (30.2002, 0.8148) (30.064, 0.8148) (29.752, 0.6475) (29.5875, 0.4887) knots 0 0 0 1 2 2 2
  spline S165 degree 2 poles (29.5875, 0.4887) (29.5904, 0.4489) (29.596, 0.3383) (29.596, 0.2646) knots 0 0 0 1 2 2 2
  line L192 (29.596, 0.2646) -> (29.596, -1.4656)
  line L193 (29.596, -1.4656) -> (29.1536, -1.4656)
  line L194 (29.1536, -1.4656) -> (29.1536, 0.0547)
  spline S166 degree 2 poles (29.1536, 0.0547) (29.1536, 0.2362) (29.1252, 0.5454) (29.0798, 0.6305) knots 0 0 0 1 2 2 2
  spline S167 degree 2 poles (29.0798, 0.6305) (29.0344, 0.7241) (28.8614, 0.8148) (28.7111, 0.8148) knots 0 0 0 1 2 2 2
  spline S168 degree 2 poles (28.7111, 0.8148) (28.5693, 0.8148) (28.2545, 0.6361) (28.107, 0.4972) knots 0 0 0 1 2 2 2
  line L195 (28.107, 0.4972) -> (28.107, -1.4656)
  line L196 (28.107, -1.4656) -> (27.6645, -1.4656)
  line L197 (27.6645, -1.4656) -> (27.6645, 1.1609)
  line L198 (27.6645, 1.1609) -> (28.107, 1.1609)
  line L199 (28.107, 1.1609) -> (28.107, 0.8716)
  spline S169 degree 2 poles (28.107, 0.8716) (28.28, 1.0446) (28.6203, 1.2346) (28.8246, 1.2346) knots 0 0 0 1 2 2 2
  spline S170 degree 2 poles (28.8246, 1.2346) (29.0571, 1.2346) (29.4173, 1.0219) (29.5109, 0.7808) knots 0 0 0 1 2 2 2
  spline S171 degree 2 poles (29.5109, 0.7808) (29.7123, 1.0049) (30.0924, 1.2346) (30.3136, 1.2346) knots 0 0 0 1 2 2 2
  spline S172 degree 2 poles (30.3136, 1.2346) (30.4838, 1.2346) (30.7617, 1.1297) (30.8639, 1.0105) knots 0 0 0 1 2 2 2
  spline S173 degree 2 poles (30.8639, 1.0105) (30.9688, 0.8914) (31.0851, 0.534) (31.0851, 0.2646) knots 0 0 0 1 2 2 2
  line L200 (31.0851, 0.2646) -> (31.0851, -1.4656)
  line L201 (31.0851, -1.4656) -> (30.6426, -1.4656)
  line L202 (34.6844, -1.4656) -> (34.6844, 0.0547)
  spline S174 degree 2 poles (34.6844, 0.0547) (34.6844, 0.2362) (34.656, 0.5454) (34.6106, 0.6305) knots 0 0 0 1 2 2 2
  spline S175 degree 2 poles (34.6106, 0.6305) (34.5652, 0.7241) (34.3922, 0.8148) (34.2419, 0.8148) knots 0 0 0 1 2 2 2
  spline S176 degree 2 poles (34.2419, 0.8148) (34.1058, 0.8148) (33.7938, 0.6475) (33.6293, 0.4887) knots 0 0 0 1 2 2 2
  spline S177 degree 2 poles (33.6293, 0.4887) (33.6321, 0.4489) (33.6378, 0.3383) (33.6378, 0.2646) knots 0 0 0 1 2 2 2
  line L203 (33.6378, 0.2646) -> (33.6378, -1.4656)
  line L204 (33.6378, -1.4656) -> (33.1953, -1.4656)
  line L205 (33.1953, -1.4656) -> (33.1953, 0.0547)
  spline S178 degree 2 poles (33.1953, 0.0547) (33.1953, 0.2362) (33.1669, 0.5454) (33.1216, 0.6305) knots 0 0 0 1 2 2 2
  spline S179 degree 2 poles (33.1216, 0.6305) (33.0762, 0.7241) (32.9032, 0.8148) (32.7528, 0.8148) knots 0 0 0 1 2 2 2
  spline S180 degree 2 poles (32.7528, 0.8148) (32.611, 0.8148) (32.2962, 0.6361) (32.1487, 0.4972) knots 0 0 0 1 2 2 2
  line L206 (32.1487, 0.4972) -> (32.1487, -1.4656)
  line L207 (32.1487, -1.4656) -> (31.7062, -1.4656)
  line L208 (31.7062, -1.4656) -> (31.7062, 1.1609)
  line L209 (31.7062, 1.1609) -> (32.1487, 1.1609)
  line L210 (32.1487, 1.1609) -> (32.1487, 0.8716)
  spline S181 degree 2 poles (32.1487, 0.8716) (32.3217, 1.0446) (32.6621, 1.2346) (32.8663, 1.2346) knots 0 0 0 1 2 2 2
  spline S182 degree 2 poles (32.8663, 1.2346) (33.0989, 1.2346) (33.4591, 1.0219) (33.5527, 0.7808) knots 0 0 0 1 2 2 2
  spline S183 degree 2 poles (33.5527, 0.7808) (33.7541, 1.0049) (34.1341, 1.2346) (34.3553, 1.2346) knots 0 0 0 1 2 2 2
  spline S184 degree 2 poles (34.3553, 1.2346) (34.5255, 1.2346) (34.8035, 1.1297) (34.9056, 1.0105) knots 0 0 0 1 2 2 2
  spline S185 degree 2 poles (34.9056, 1.0105) (35.0105, 0.8914) (35.1268, 0.534) (35.1268, 0.2646) knots 0 0 0 1 2 2 2
  line L211 (35.1268, 0.2646) -> (35.1268, -1.4656)
  line L212 (35.1268, -1.4656) -> (34.6844, -1.4656)
  point P0 (93, 0)
  dimension "d63" = 88.8221
  dimension "d64" = 4.5
  dimension "d67" = 40
  constraints: 1 parallel, 3 other
  measures "d63" distance of L1.end L2.end
  measures "d64" distance of L0.end L1.end
  measures "d67" distance between parallel lines of L3 L5
emboss "Prägen1" sketch "Skizze10" operation cut depth 0.1 direction (0, -1, 0) wrap yes faces at (124.1667, 9.9676, -0.8047) contours L13 L14 L15 L16 L17 L18 L4 L7 L8 L10 L11 | L4 L11 L12 L13 | L4 L8 L9 L10 | L4 L18 L6 L7 | L26 L27 L28 L29 L30 L31 L4 L20 L21 L23 L24 | L4 L24 L25 L26 | L4 L21 L22 L23 | L4 L31 L19 L20 | S1 S2 S3 S0 L4 S4 S5 S6 S7 S8 S9 | L4 S9 S10 S11 S4 S0 S1 | S19 S20 S21 L34 L35 L36 L37 L38 S22 S23 S24 L4 | L4 S24 S12 S13 S14 L32 L33 S15 S16 S17 S18 S19 | S32 S33 S34 L41 L42 L43 L44 L45 S35 S36 S37 L4 | L4 S37 S25 S26 S27 L39 L40 S28 S29 S30 S31 S32 | S45 S46 S47 L48 L49 L50 L51 L52 S48 S49 S50 L4 | L4 S50 S38 S39 S40 L46 L47 S41 S42 S43 S44 S45 | L53 L54 L55 L4 L61 L62 | L4 L62 L63 L61 L55 L56 L57 L58 L59 L60 L53 | L68 L69 L70 L4 L65 L66 | L4 L66 L67 L68 | L4 L70 L71 L73 L64 L65 | L71 L72 L73 L4 | S52 S53 S54 S55 S56 L76 L77 S57 S58 S59 S60 L4 | L4 S60 S61 L78 L79 L74 L75 S51 S52 | S63 S64 S65 S62 L4 S66 S67 S68 S69 S70 S71 | L4 S71 S72 S73 S66 S62 S63 | S75 S76 S77 S74 L4 S78 S79 S80 S81 S82 S83 | L4 S83 S84 S85 S78 S74 S75 | S87 S88 S89 S90 S91 L84 L85 S92 S93 S94 S95 L4 | L4 S95 S96 S97 L86 L87 L88 L90 S98 S99 S86 S87 | L88 L89 L90 L4 | L94 L95 L96 S100 L97 L98 L4 | L4 L98 L99 L100 L91 L92 L93 L94 | L104 L105 L106 S101 L107 L108 L4 | L4 L108 L109 L110 L101 L102 L103 L104 | L114 L115 L116 L117 L118 L119 L120 L4 | L4 L120 L121 L122 L111 L112 L113 L114 | L127 L128 L129 S105 S106 L130 L4 L124 S102 S103 S104 L125 | L4 L125 L126 L127 | L4 L130 L123 L124 | L135 L136 L137 S110 S111 L138 L4 L132 S107 S108 S109 L133 | L4 L133 L134 L135 | L4 L138 L131 L132 | S113 S114 S115 L139 L4 | L4 L139 L140 S116 S117 S118 L141 L142 S119 S120 S112 S113 | L148 L149 L150 S128 S129 L151 L4 L145 S125 S126 S127 L146 | L4 L146 L147 L148 | L4 L151 L144 L145 | S132 S133 S134 L155 L156 L157 S135 S130 L4 S138 S136 L158 L159 S139 S140 S141 | L4 S141 L159 L158 S137 S138 S130 S131 L152 L153 L154 S132 | L171 L172 L173 S142 L174 L175 L4 | L4 L175 L176 L177 L168 L169 L170 L171 | S146 S147 S148 S149 L178 L179 S150 S151 S152 S153 S154 L4 S155 S156 S157 S158 | L4 S158 S159 S160 S161 S155 S154 S143 S144 S145 S146 | L186 L187 L188 L189 L190 L184 L4 | L4 L184 L185 L186 | L197 L198 L199 S169 S170 S171 S172 S173 L200 L4 L191 S162 S163 S164 S165 L192 L194 S166 S167 S168 L195 | L4 L195 L196 L197 | L4 L192 L193 L194 | L4 L200 L201 L191 | L208 L209 L210 S181 S182 S183 S184 S185 L211 L4 L202 S174 S175 S176 S177 L203 L205 S178 S179 S180 L206 | L4 L206 L207 L208 | L4 L203 L204 L205 | L4 L211 L212 L202 | L80 L81 L82 L83 | L160 L161 L162 L163 | L164 L165 L166 L167 | L180 L181 L182 L183
fillet "Rundung1" radius 1 1 edges at (199.9388, 0, -8.35)
equation "\"RBGBDIM_01\" = 0"
equation "\"RBGBDIM_02\" = 0"
equation "\"RBGBDIM_03\" = 0"
equation "\"RBGBDIM_04\" = 0"
